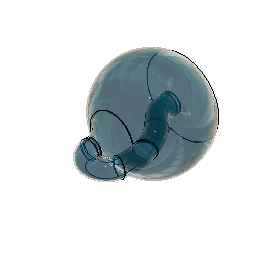
Klein Bottle v1 (Autodesk Fusion 360 design; units mm, degrees)
Autodesk Fusion 360 part; units mm, degrees
sketch "Sketch1" plane through (0, 0, 0) normal (0, 0, 1) x (1, 0, 0)
  line L0 (0, 15) -> (35, 15)
  line L1 (35, 15) -> (22, 27)
  line L2 (22, 27) -> (0, 15)
  constraint horizontal L0
sketch "Sketch2" plane through (0, 0, 0) normal (0, 0, 1) x (1, 0, 0)
  line L0 (0, 0) -> (30.1059, 0) construction
  line L1 (0, 0) -> (0, -150)
  line L2 (0, -150) -> (15, -150) construction
  line L3 (15, -150) -> (15, -145)
  arc A0 (35.5239, -113.3946) -> (15, -145) centre (49.597, -145) ccw
  arc A1 (35.5239, -113.3946) -> (60.024, 5.9981) centre (5.0374, -44.9285) ccw
  line L4 (0, -17.4327) -> (13, -17.4327) construction
  line L5 (13, -17.4327) -> (13, -12.4327)
  arc A2 (60.024, 5.9981) -> (13, -12.4327) centre (40.1239, -12.4327) ccw
  line L6 (15, -17.4327) -> (15, -12.4327)
  arc A3 (58.5567, 4.6391) -> (15, -12.4327) centre (40.1239, -12.4327) ccw
  arc A4 (34.7103, -111.5676) -> (58.5567, 4.6391) centre (5.0374, -44.9285) ccw
  arc A5 (34.7103, -111.5676) -> (13, -145) centre (49.597, -145) ccw
  line L7 (13, -150) -> (13, -145)
  line L8 (13, -17.4327) -> (15, -17.4327)
  line L9 (13, -150) -> (15, -150)
  dimension "d5" = 150
  dimension "d6" = 15
  dimension "d7" = 5
  dimension "d8" = 13
  dimension "d9" = 5
  dimension "d10" = -2
  constraint coincident L0.start L1.start
  constraint horizontal L0
  constraint perpendicular L0 L1
  constraint perpendicular L1 L2
  constraint perpendicular L2 L3
  constraint tangent L3 A0
  constraint tangent A0 A1
  constraint coincident L1 L4.start
  constraint perpendicular L1 L4
  constraint perpendicular L4 L5
  constraint tangent L5 A2
  constraint tangent A1 A2
  constraint perpendicular L3 L9
  measures "d5" distance of L0.start L1.end
  measures "d6" distance of L1.end L2.end
  measures "d7" distance of L2.end L3.end
  measures "d8" distance of L4.start L4.end
  measures "d9" distance of L4.end L5.end
revolve "Revolve1" add sketch "Sketch2" angle 360 about axis through (0, 0, 0) along (0, -1, 0)
sketch "Sketch3" plane through (0, 0, 0) normal (0, 0, 1) x (1, 0, 0)
  line L0 (33.6413, -150) -> (-12.5132, -150) construction
  arc A0 (0, -150) -> (49.461, -150) centre (24.7305, -146.3392) ccw
  line L1 (0, 0) -> (0, -214.5491) construction
  arc A1 (49.461, -150) -> (24.8053, -62.6917) centre (-60.0481, -133.7897) ccw
  spline S0 degree 5 poles (24.8053, -62.6917) (22.5587, -60.0105) (18.39, -55.1271) (13.1092, -49.2378) (7.7788, -43.6753) (3.2569, -37.9519) (1.0476, -32.0488) (0.1906, -25.6766) (0, -20.3591) (0, -17.4327) knots 0 0 0 0 0 0 0.2 0.4 0.6 0.8 1 1 1 1 1 1
  line L2 (-13, -17.4327) -> (13, -17.4327)
  line L3 (0, -23.0799) -> (0, -11.7854)
  line L4 (29.3637, -68.132) -> (20.2469, -57.2513)
  point P0 (0, -150)
  dimension "d12" = 150
  dimension "d13" = 25
  constraint horizontal L0
  constraint coincident L0 P0
  constraint coincident L0 A0.end
  constraint coincident P0 A0.start
  constraint coincident L1.start origin
  constraint perpendicular L0 L1
  constraint coincident P0 L1
  constraint tangent A0 A1
  constraint coincident L1 S0.end
  constraint coincident S0.end L2
  constraint midpoint S0.end L3
  constraint coincident L1 L3.start
  constraint midpoint A1.end L4
  constraint tangent A1 L4
  measures "d12" distance of L1.start A0.start
  measures "d13" radius of A0
sketch "Sketch4" plane through (0, -150, 0) normal (0, -1, 0) x (1, 0, 0)
  circle A0 centre (0, 0) radius 15
  circle A1 centre (0, 0) radius 13
  circle A2 centre (0, 0) radius 13
  constraint concentric A0 A2
sweep "Sweep3" cut profiles "Sketch4" path "Sketch3" along A0 A1 section 1 contours A1 A2
sweep "Sweep4" add 1 faces at (14.2291, -150, -1.3911) path "Sketch3" along A0 A1 S0
